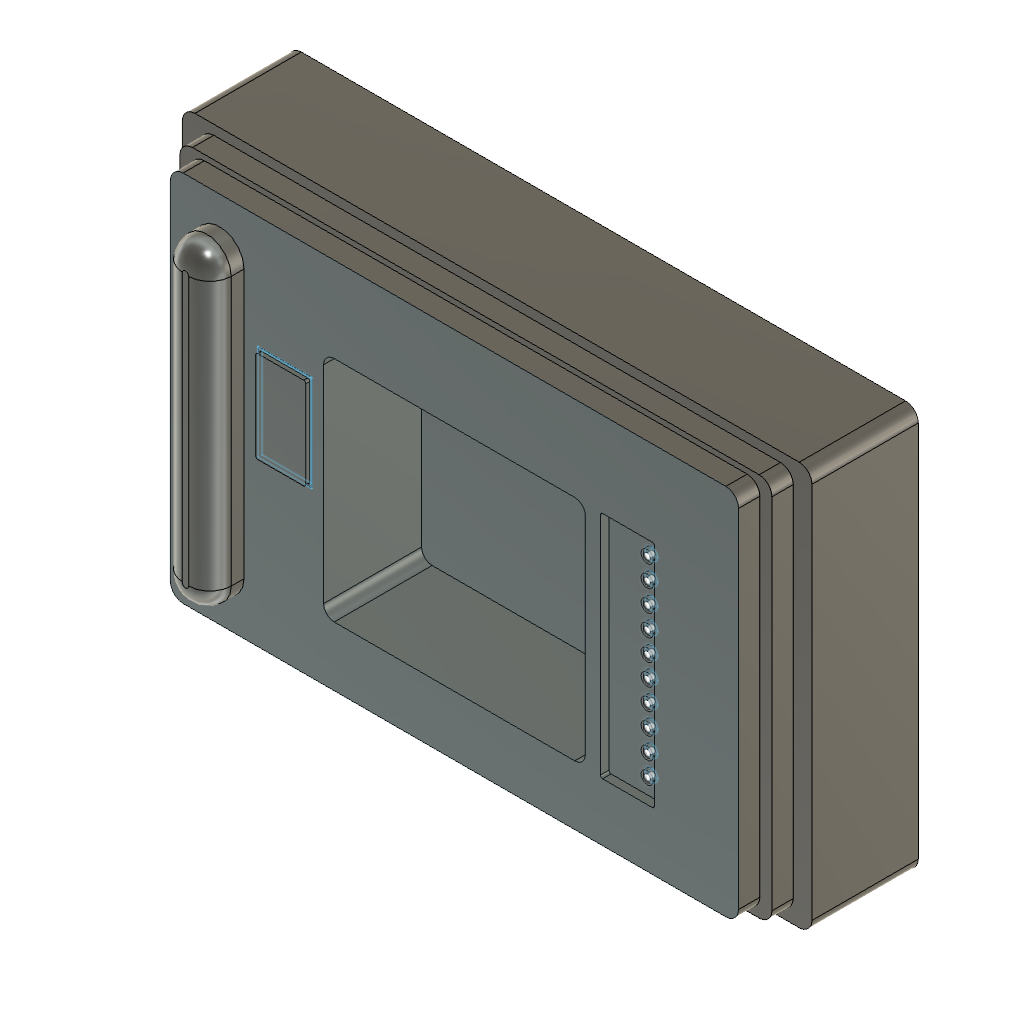
radar (Autodesk Fusion 360 design; units mm, degrees)
part number: 2026-11-02-20-23-44-263
Autodesk Fusion 360 part; units mm, degrees
sketch "screen" plane through (0, 0, 0) normal (0, 1, 0) x (1, 0, 0)
  line L0 (-50.0347, -23.9941) -> (11.4653, -23.9941)
  line L1 (11.4653, -23.9941) -> (11.4653, 29.6059)
  line L2 (11.4653, 29.6059) -> (-50.0347, 29.6059)
  line L3 (-50.0347, 29.6059) -> (-50.0347, -23.9941)
  dimension "d1" = 61.5
  dimension "d2" = 53.6
  constraint horizontal L0
  constraint vertical L1
  constraint horizontal L2
  constraint vertical L3
  measures "d1" distance of L0.start L0.end
  measures "d2" distance of L0.start L2.end
sketch "shell" plane through (0, 0, 0) normal (0, 1, 0) x (-1, 0, 0)
  line L0 (86.0395, 43.9923) -> (-47.4605, 43.9923)
  line L1 (-47.4605, 43.9923) -> (-47.4605, -43.6077)
  line L2 (-47.4605, -43.6077) -> (86.0395, -43.6077)
  line L3 (86.0395, -43.6077) -> (86.0395, 43.9923)
  dimension "d3" = 133.5
  dimension "d4" = 87.6
  constraint horizontal L0
  constraint vertical L1
  constraint horizontal L2
  constraint vertical L3
  measures "d3" distance of L0.start L0.end
  measures "d4" distance of L0.start L2.end
extrude "Extrude1" add sketch "shell" along normal blind 5 makes body 1
sketch "1st shell extrude" plane through (0, 5, 0) normal (0, 1, 0) x (-1, 0, 0)
  line L0 (86.0395, -43.6077) -> (86.0395, 43.9923)
  line L1 (86.0395, 43.9923) -> (-47.4605, 43.9923)
  line L2 (-47.4605, 43.9923) -> (-47.4605, -43.6077)
  line L3 (-47.4605, -43.6077) -> (86.0395, -43.6077)
  line L4 (-50.2932, 45.2731) -> (88.8398, 45.2731)
  line L5 (88.8398, 45.2731) -> (88.8398, -44.9576)
  line L6 (88.8398, -44.9576) -> (-50.2932, -44.9576)
  line L7 (-50.2932, -44.9576) -> (-50.2932, 45.2731)
  constraint horizontal L4
  constraint vertical L5
  constraint horizontal L6
  constraint vertical L7
extrude "Extrude2" add sketch "1st shell extrude" along normal blind 5 contours L0 L1 L2 L3 | L4 L5 L6 L7 bodies 1
sketch "2nd shell extrude" plane through (0, 10, 0) normal (0, 1, 0) x (-1, 0, 0)
  line L0 (-50.2932, -44.9576) -> (88.8398, -44.9576)
  line L1 (88.8398, -44.9576) -> (88.8398, 45.2731)
  line L2 (88.8398, 45.2731) -> (-50.2932, 45.2731)
  line L3 (-50.2932, 45.2731) -> (-50.2932, -44.9576)
  line L4 (-54.7046, 47.5235) -> (93.2505, 47.5235)
  line L5 (93.2505, 47.5235) -> (93.2505, -47.2096)
  line L6 (93.2505, -47.2096) -> (-54.7046, -47.2096)
  line L7 (-54.7046, -47.2096) -> (-54.7046, 47.5235)
  constraint horizontal L4
  constraint vertical L5
  constraint horizontal L6
  constraint vertical L7
extrude "Extrude3" add sketch "2nd shell extrude" along normal blind 25 contours L0 L1 L2 L3 | L4 L5 L6 L7 bodies 1
fillet "Fillet1" radius 3 12 edges at (47.4605, 2.5, 43.9923) (50.2932, 7.5, 45.2731) (54.7046, 22.5, 47.5235) (54.7046, 22.5, -47.2096) (50.2932, 7.5, -44.9576) (47.4605, 2.5, -43.6077) (-86.0395, 2.5, 43.9923) (-88.8398, 7.5, 45.2731) (-93.2505, 22.5, 47.5235) (-93.2505, 22.5, -47.2096) (-88.8398, 7.5, -44.9576) (-86.0395, 2.5, -43.6077) on bodies 1
extrude "Extrude4" cut sketch "screen" along normal blind 23 bodies 1
sketch "Sketch7" plane through (0, 0, 0) normal (0, -1, 0) x (1, 0, 0)
  line L0 (11.4653, -29.6059) -> (-50.0347, -29.6059)
  line L1 (-50.0347, -29.6059) -> (-50.0347, 23.9941)
  line L2 (-50.0347, 23.9941) -> (11.4653, 23.9941)
  line L3 (11.4653, 23.9941) -> (11.4653, -29.6059)
  arc A0 (-86.0395, -40.6077) -> (-83.0395, -43.6077) centre (-83.0395, -40.6077) ccw
  line L4 (-83.0395, -43.6077) -> (44.4605, -43.6077)
  arc A1 (44.4605, -43.6077) -> (47.4605, -40.6077) centre (44.4605, -40.6077) ccw
  line L5 (47.4605, -40.6077) -> (47.4605, 40.9923)
  arc A2 (47.4605, 40.9923) -> (44.4605, 43.9923) centre (44.4605, 40.9923) ccw
  line L6 (44.4605, 43.9923) -> (-83.0395, 43.9923)
  arc A3 (-83.0395, 43.9923) -> (-86.0395, 40.9923) centre (-83.0395, 40.9923) ccw
  line L7 (-86.0395, 40.9923) -> (-86.0395, -40.6077)
  line L8 (15, 24) -> (27.707, 24)
  line L9 (27.707, 24) -> (27.707, -29.9957)
  line L10 (27.707, -29.9957) -> (15, -29.9957)
  line L11 (15, -29.9957) -> (15, 24)
  constraint horizontal L8
  constraint vertical L9
  constraint horizontal L10
  constraint vertical L11
extrude "Extrude5" cut sketch "Sketch7" against normal blind 2 contours L8 L9 L10 L11 bodies 1
sketch "Sketch8" plane through (0, 2, 0) normal (0, -1, 0) x (1, 0, 0)
  line L0 (15, -29.9957) -> (27.707, -29.9957)
  line L1 (27.707, -29.9957) -> (27.707, 24)
  line L2 (27.707, 24) -> (15, 24)
  line L3 (15, 24) -> (15, -29.9957)
sketch "Sketch9" plane through (0, 2, 0) normal (0, -1, 0) x (1, 0, 0)
  circle A0 centre (24.9828, 19.491) radius 1.4375
  circle A1 centre (24.9828, 19.491) radius 0.7383
  circle A2 centre (24.9828, 14.491) radius 1.4375
  circle A3 centre (24.9828, 14.491) radius 0.7383
  circle A4 centre (24.9828, 9.491) radius 1.4375
  circle A5 centre (24.9828, 9.491) radius 0.7383
  circle A6 centre (24.9828, 4.491) radius 0.7383
  circle A7 centre (24.9828, 4.491) radius 1.4375
  circle A8 centre (24.9828, -0.509) radius 0.7383
  circle A9 centre (24.9828, -0.509) radius 1.4375
  circle A10 centre (24.9828, -5.509) radius 1.4375
  circle A11 centre (24.9828, -5.509) radius 0.7383
  circle A12 centre (24.9828, -10.509) radius 0.7383
  circle A13 centre (24.9828, -10.509) radius 1.4375
  circle A14 centre (24.9828, -15.509) radius 0.7383
  circle A15 centre (24.9828, -15.509) radius 1.4375
  circle A16 centre (24.9828, -20.509) radius 0.7383
  circle A17 centre (24.9828, -20.509) radius 1.4375
  circle A18 centre (24.9828, -25.509) radius 0.7383
  circle A19 centre (24.9828, -25.509) radius 1.4375
  constraint concentric A0 A1
  constraint concentric A2 A3
  constraint concentric A4 A5
  constraint concentric A6 A7
  constraint concentric A8 A9
  constraint concentric A10 A11
  constraint concentric A12 A13
  constraint concentric A14 A15
  constraint concentric A16 A17
  constraint concentric A18 A19
extrude "Extrude6" cut sketch "Sketch9" against normal blind 2 contours A1 | A3 | A5 | A6 | A8 | A11 | A12 | A14 | A16 | A18 bodies 1
extrude "Extrude7" add sketch "Sketch9" along normal blind 1 bodies 1
fillet "Fillet2" radius 2.5 4 edges at (11.4653, 11.5, 23.9941) (11.4653, 11.5, -29.6059) (-50.0347, 11.5, 23.9941) (-50.0347, 11.5, -29.6059) on bodies 1
fillet "Fillet3" radius 0.5 4 edges at (15, 1, 24) (27.707, 1, 24) (15, 1, -29.9957) (27.707, 1, -29.9957) on bodies 1
sketch "Sketch10" plane through (0, 0, 0) normal (0, -1, 0) x (1, 0, 0)
  line L0 (27.707, 23.5) -> (27.707, -29.4957)
  arc A0 (27.207, -29.9957) -> (27.707, -29.4957) centre (27.207, -29.4957) ccw
  line L1 (27.207, -29.9957) -> (15.5, -29.9957)
  arc A1 (15, -29.4957) -> (15.5, -29.9957) centre (15.5, -29.4957) ccw
  line L2 (15, -29.4957) -> (15, 23.5)
  arc A2 (15.5, 24) -> (15, 23.5) centre (15.5, 23.5) ccw
  line L3 (15.5, 24) -> (27.207, 24)
  arc A3 (27.707, 23.5) -> (27.207, 24) centre (27.207, 23.5) ccw
  line L4 (8.9653, -29.6059) -> (-47.5347, -29.6059)
  arc A4 (-50.0347, -27.1059) -> (-47.5347, -29.6059) centre (-47.5347, -27.1059) ccw
  line L5 (-50.0347, -27.1059) -> (-50.0347, 21.4941)
  arc A5 (-47.5347, 23.9941) -> (-50.0347, 21.4941) centre (-47.5347, 21.4941) ccw
  line L6 (-47.5347, 23.9941) -> (8.9653, 23.9941)
  arc A6 (11.4653, 21.4941) -> (8.9653, 23.9941) centre (8.9653, 21.4941) ccw
  line L7 (11.4653, 21.4941) -> (11.4653, -27.1059)
  arc A7 (8.9653, -29.6059) -> (11.4653, -27.1059) centre (8.9653, -27.1059) ccw
  arc A8 (-86.0395, -40.6077) -> (-83.0395, -43.6077) centre (-83.0395, -40.6077) ccw
  line L8 (-83.0395, -43.6077) -> (44.4605, -43.6077)
  arc A9 (44.4605, -43.6077) -> (47.4605, -40.6077) centre (44.4605, -40.6077) ccw
  line L9 (47.4605, -40.6077) -> (47.4605, 40.9923)
  arc A10 (47.4605, 40.9923) -> (44.4605, 43.9923) centre (44.4605, 40.9923) ccw
  line L10 (44.4605, 43.9923) -> (-83.0395, 43.9923)
  arc A11 (-83.0395, 43.9923) -> (-86.0395, 40.9923) centre (-83.0395, 40.9923) ccw
  line L11 (-86.0395, 40.9923) -> (-86.0395, -40.6077)
  line L12 (-64.7948, 16.8922, -0.3084) -> (-53.2922, 16.8922, -0.3084)
  line L13 (-53.2922, 16.8922, -0.3084) -> (-53.2922, -4.3888, -0.3084)
  line L14 (-53.2922, -4.3888, -0.3084) -> (-64.7948, -4.3888, -0.3084)
  line L15 (-64.7948, -4.3888, -0.3084) -> (-64.7948, 16.8922, -0.3084)
sketch "Sketch12" plane through (0, 0, 0) normal (0, -1, 0) x (1, 0, 0)
  line L0 (-65.3669, 17.4864, 0.0453) -> (-52.7934, 17.4864, 0.0453)
  line L1 (-52.7934, 17.4864, 0.0453) -> (-52.7934, -4.9548, 0.0453)
  line L2 (-52.7934, -4.9548, 0.0453) -> (-65.3669, -4.9548, 0.0453)
  line L3 (-65.3669, -4.9548, 0.0453) -> (-65.3669, 17.4864, 0.0453)
extrude "Extrude8" add sketch "Sketch12" against normal blind 1 separate body contours L0 L1 L2 L3 in plane through (0, -0.0453, 0) normal (0, -1, 0) makes body 2
sketch "Sketch13" plane through (0, 0, 0) normal (0, 1, 0) x (1, 0, 0)
  line L0 (-65, -17) -> (-53.2285, -17)
  line L1 (-53.2285, -17) -> (-53.2285, 4.5276)
  line L2 (-53.2285, 4.5276) -> (-65, 4.5276)
  line L3 (-65, 4.5276) -> (-65, -17)
  constraint horizontal L0
  constraint vertical L1
  constraint horizontal L2
  constraint vertical L3
extrude "Extrude9" add sketch "Sketch13" against normal blind 1 bodies 1 2
sketch "Sketch14" plane through (0, 0, 0) normal (0, 1, 0) x (1, 0, 0)
fillet "Fillet4" radius 0.5 4 edges at (-65, -0.5227, 17) (-65, -0.5227, -4.5276) (-53.2285, -0.5227, -4.5276) (-53.2285, -0.5227, 17) on bodies 1
sketch "Sketch15" plane through (0, 0, 0) normal (0, 1, 0) x (1, 0, 0)
  circle A0 centre (-74.4846, -31.6157) radius 5.7606
  circle A1 centre (-74.4846, 31.3843) radius 5.7606
  line L0 (-80.2347, -31.9627) -> (-68.724, -31.9627)
  line L1 (-68.724, -31.9627) -> (-68.724, 31.3843)
  line L2 (-68.724, 31.3843) -> (-80.2347, 31.3843)
  line L3 (-80.2347, 31.3843) -> (-80.2347, -31.9627)
  constraint horizontal L0
  constraint vertical L1
  constraint horizontal L2
  constraint vertical L3
  constraint coincident A1 L1.end
  constraint coincident A0 L0.start
extrude "Extrude10" add sketch "Sketch15" against normal blind 8 contours A0 L0 L3 | A0 A1 L1 L3 | A0 L0 | A1 L2 L3 | A1 L2 L3 bodies 1
fillet "Fillet5" radius 5 4 edges at (-74.6582, -8, -37.1423) (-68.724, -8, 0.1157) (-74.3109, -8, 37.3736) (-80.2347, -8, 0.4627) on bodies 1
